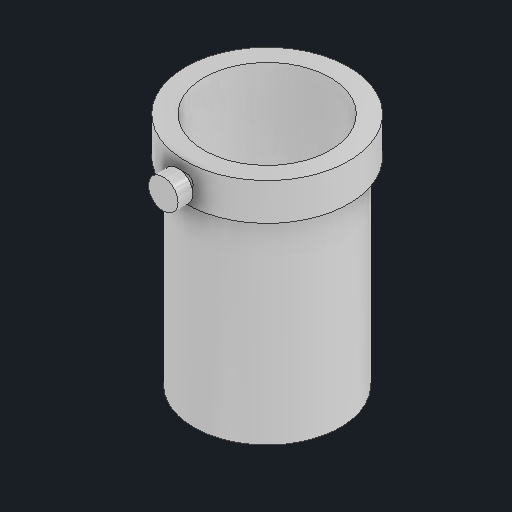
# Autodesk Inventor part: c8n_focuser_drawtube
Saved by Autodesk Inventor 2027.1 (Build 311270010, 270A)
## iProperties
Created: 2026-11-04
Part Number: c8n_focuser_drawtube
Material: Generic
Description: 2 in drawtube with compression collar
Document SubType Name: Modeling
Designer: Claude (from photos)
Density: 1 g/cm^3
Appearance: Aluminum - Polished
Author: alexg
Autodesk Inventor part; units mm, degrees
ref_plane "Work Plane1" through (0, 105, 0) normal (0, 1, 0) x (-1, 0, 0)
sketch "Drawtube sketch" plane through (0, 105, 0) normal (0, 1, 0) x (-1, 0, 0)
  circle A0 centre (-842, 0) radius 29.6
  circle A1 centre (-842, 0) radius 25.5
  constraints: 2 centre point
extrude "Drawtube" add sketch "Drawtube sketch" along normal blind 80
ref_plane "Work Plane2" through (0, 185, 0) normal (0, 1, 0) x (-1, 0, 0)
sketch "2 in collar sketch" plane through (0, 185, 0) normal (0, 1, 0) x (-1, 0, 0)
  circle A0 centre (-842, 0) radius 33
  circle A1 centre (-842, 0) radius 25.5
  constraints: 2 centre point
extrude "2 in collar" add sketch "2 in collar sketch" along normal blind 15
ref_plane "Work Plane3" through (0, 0, 32) normal (0, 0, 1) x (1, 0, 0)
sketch "Collar screw sketch" plane through (0, 0, 32) normal (0, 0, 1) x (1, 0, 0)
  circle A0 centre (842, 193) radius 3
  constraints: 1 centre point
extrude "Collar screw" add sketch "Collar screw sketch" along normal blind 6
ref_plane "Work Plane4" through (0, 0, 36) normal (0, 0, 1) x (1, 0, 0)
sketch "Collar thumbscrew sketch" plane through (0, 0, 36) normal (0, 0, 1) x (1, 0, 0)
  circle A0 centre (842, 193) radius 6
  constraints: 1 centre point
extrude "Collar thumbscrew" add sketch "Collar thumbscrew sketch" along normal blind 6
body "Solid1"
